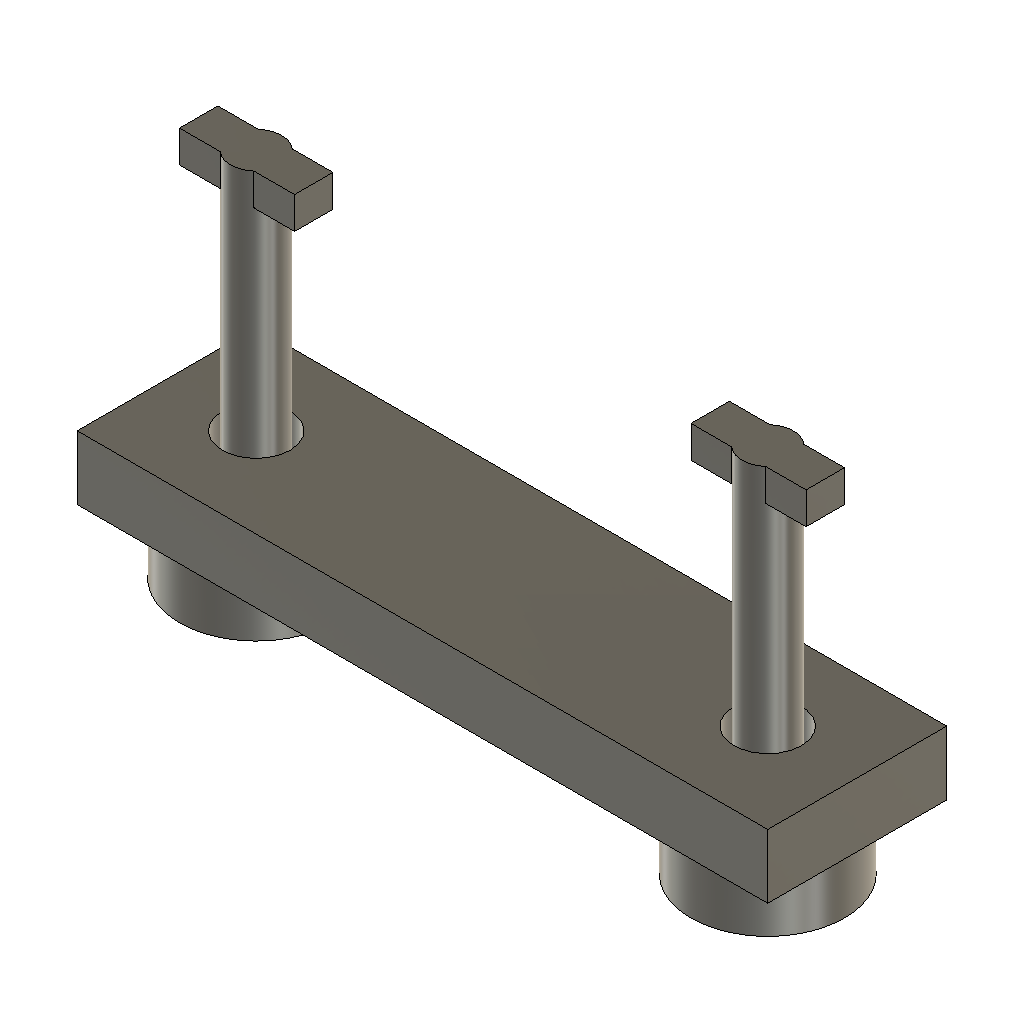
panel-handling-tool-concept (Autodesk Fusion 360 design; units mm, degrees)
part number: 2026-10-31-10-05-27-042
part number: 2026-10-31-10-05-27-360
part number: 2026-10-31-10-05-27-543
part number: 2026-10-31-10-05-28-223
part number: 2026-10-31-10-05-28-987
part number: 2026-10-31-10-05-30-686
part number: 2026-10-31-10-05-32-516
part number: 2026-10-31-10-05-34-265
Autodesk Fusion 360 part; units mm, degrees
ref_plane "WorkPlane1" through (0, 0, -16) normal (0, 0, 1) x (1, 0, 0) in component "PRINT handle bridge"
sketch "Front handle bridge sketch" plane through (0, 0, -16) normal (0, 0, 1) x (1, 0, 0) in component "PRINT handle bridge"
  line L0 (-7, -7) -> (47, -7)
  line L1 (47, -7) -> (47, 7)
  line L2 (47, 7) -> (-7, 7)
  line L3 (-7, 7) -> (-7, -7)
  dimension "d70" = 7
  dimension "d71" = 7
  dimension "d72" = 54
  dimension "d73" = 14
  constraint horizontal L0
  constraint vertical L1
  constraint horizontal L2
  constraint vertical L3
  measures "d70" horizontal distance of origin L0.start
  measures "d71" vertical distance of origin L0.start
  measures "d72" horizontal distance of L0.start L0.end
  measures "d73" vertical distance of L0.end L1.end
extrude "Front handle bridge" add sketch "Front handle bridge sketch" along normal blind 5 makes body 1 in component "PRINT handle bridge"
ref_plane "WorkPlane2" through (0, 0, -16) normal (0, 0, 1) x (1, 0, 0) in component "PRINT handle bridge"
sketch "Rotating key and assembly clearance sketch" plane through (0, 0, -16) normal (0, 0, 1) x (1, 0, 0) in component "PRINT handle bridge"
  circle A0 centre (0, 0) radius 2.65
  dimension "d78" = 5.3
  constraint coincident A0.centre origin
  measures "d78" diameter of A0
extrude "Rotating key and assembly clearance" cut sketch "Rotating key and assembly clearance sketch" along normal blind 5 bodies 1 in component "PRINT handle bridge"
ref_plane "WorkPlane1" through (0, 0, -16) normal (0, 0, 1) x (1, 0, 0) in component "PRINT quarter-turn key 0 mm"
sketch "Key shaft sketch" plane through (0, 0, -16) normal (0, 0, 1) x (1, 0, 0) in component "PRINT quarter-turn key 0 mm"
  circle A0 centre (0, 0) radius 2
  dimension "d83" = 4
  constraint coincident A0.centre origin
  measures "d83" diameter of A0
extrude "Key shaft" add sketch "Key shaft sketch" along normal blind 24 separate body makes body 2 in component "PRINT quarter-turn key 0 mm"
ref_plane "WorkPlane2" through (0, 0, -18) normal (0, 0, 1) x (1, 0, 0) in component "PRINT quarter-turn key 0 mm"
sketch "Square knob drive sketch" plane through (0, 0, -18) normal (0, 0, 1) x (1, 0, 0) in component "PRINT quarter-turn key 0 mm"
  line L0 (-1.8, -1.8) -> (1.8, -1.8)
  line L1 (1.8, -1.8) -> (1.8, 1.8)
  line L2 (1.8, 1.8) -> (-1.8, 1.8)
  line L3 (-1.8, 1.8) -> (-1.8, -1.8)
  dimension "d88" = 1.8
  dimension "d89" = 1.8
  dimension "d90" = 3.6
  dimension "d91" = 3.6
  constraint horizontal L0
  constraint vertical L1
  constraint horizontal L2
  constraint vertical L3
  measures "d88" horizontal distance of origin L0.start
  measures "d89" vertical distance of origin L0.start
  measures "d90" horizontal distance of L0.start L0.end
  measures "d91" vertical distance of L0.end L1.end
extrude "Square knob drive" add sketch "Square knob drive sketch" along normal blind 2 bodies 2 in component "PRINT quarter-turn key 0 mm"
ref_plane "WorkPlane3" through (0, 0, -18) normal (0, 0, 1) x (1, 0, 0) in component "PRINT quarter-turn key 0 mm"
sketch "M2 pilot - tapping trial required sketch" plane through (0, 0, -18) normal (0, 0, 1) x (1, 0, 0) in component "PRINT quarter-turn key 0 mm"
  circle A0 centre (0, 0) radius 0.8
  dimension "d96" = 1.6
  constraint coincident A0.centre origin
  measures "d96" diameter of A0
extrude "M2 pilot - tapping trial required" cut sketch "M2 pilot - tapping trial required sketch" along normal blind 6 bodies 2 in component "PRINT quarter-turn key 0 mm"
ref_plane "WorkPlane4" through (0, 0, 5.5) normal (0, 0, 1) x (1, 0, 0) in component "PRINT quarter-turn key 0 mm"
sketch "Locked transverse bearing tab sketch" plane through (0, 0, 5.5) normal (0, 0, 1) x (1, 0, 0) in component "PRINT quarter-turn key 0 mm"
  line L0 (-4.5, -1.5) -> (4.5, -1.5)
  line L1 (4.5, -1.5) -> (4.5, 1.5)
  line L2 (4.5, 1.5) -> (-4.5, 1.5)
  line L3 (-4.5, 1.5) -> (-4.5, -1.5)
  dimension "d101" = 4.5
  dimension "d102" = 1.5
  dimension "d103" = 9
  dimension "d104" = 3
  constraint horizontal L0
  constraint vertical L1
  constraint horizontal L2
  constraint vertical L3
  measures "d101" horizontal distance of origin L0.start
  measures "d102" vertical distance of origin L0.start
  measures "d103" horizontal distance of L0.start L0.end
  measures "d104" vertical distance of L0.end L1.end
extrude "Locked transverse bearing tab" add sketch "Locked transverse bearing tab sketch" along normal blind 2.5 bodies 2 in component "PRINT quarter-turn key 0 mm"
ref_plane "WorkPlane1" through (0, 0, -21) normal (0, 0, 1) x (1, 0, 0) in component "PRINT thumb knob 0 mm"
sketch "Separate thumb knob sketch" plane through (0, 0, -21) normal (0, 0, 1) x (1, 0, 0) in component "PRINT thumb knob 0 mm"
  circle A0 centre (0, 0) radius 6
  dimension "d109" = 12
  constraint coincident A0.centre origin
  measures "d109" diameter of A0
extrude "Separate thumb knob" add sketch "Separate thumb knob sketch" along normal blind 5 separate body makes body 3 in component "PRINT thumb knob 0 mm"
ref_plane "WorkPlane2" through (0, 0, -16) normal (0, 0, 1) x (1, 0, 0) in component "PRINT thumb knob 0 mm"
sketch "Square drive socket sketch" plane through (0, 0, -16) normal (0, 0, 1) x (1, 0, 0) in component "PRINT thumb knob 0 mm"
  line L0 (-1.9, -1.9) -> (1.9, -1.9)
  line L1 (1.9, -1.9) -> (1.9, 1.9)
  line L2 (1.9, 1.9) -> (-1.9, 1.9)
  line L3 (-1.9, 1.9) -> (-1.9, -1.9)
  dimension "d114" = 1.9
  dimension "d115" = 1.9
  dimension "d116" = 3.8
  dimension "d117" = 3.8
  constraint horizontal L0
  constraint vertical L1
  constraint horizontal L2
  constraint vertical L3
  measures "d114" horizontal distance of origin L0.start
  measures "d115" vertical distance of origin L0.start
  measures "d116" horizontal distance of L0.start L0.end
  measures "d117" vertical distance of L0.end L1.end
extrude "Square drive socket" cut sketch "Square drive socket sketch" against normal blind 2.2 bodies 3 in component "PRINT thumb knob 0 mm"
ref_plane "WorkPlane3" through (0, 0, -21) normal (0, 0, 1) x (1, 0, 0) in component "PRINT thumb knob 0 mm"
sketch "M2 fixing clearance sketch" plane through (0, 0, -21) normal (0, 0, 1) x (1, 0, 0) in component "PRINT thumb knob 0 mm"
  circle A0 centre (0, 0) radius 1.2
  dimension "d122" = 2.4
  constraint coincident A0.centre origin
  measures "d122" diameter of A0
extrude "M2 fixing clearance" cut sketch "M2 fixing clearance sketch" along normal blind 5 bodies 3 in component "PRINT thumb knob 0 mm"
ref_plane "WorkPlane4" through (0, 0, -21) normal (0, 0, 1) x (1, 0, 0) in component "PRINT thumb knob 0 mm"
sketch "M2 flush head recess sketch" plane through (0, 0, -21) normal (0, 0, 1) x (1, 0, 0) in component "PRINT thumb knob 0 mm"
  circle A0 centre (0, 0) radius 2
  dimension "d127" = 4
  constraint coincident A0.centre origin
  measures "d127" diameter of A0
extrude "M2 flush head recess" cut sketch "M2 flush head recess sketch" along normal blind 0.8 draft -45 bodies 3 in component "PRINT thumb knob 0 mm"
ref_plane "WorkPlane1" through (0, 0, -20.9) normal (0, 0, 1) x (1, 0, 0) in component "REFERENCE handle M2x6 0 mm"
sketch "Nominal 90 degree head sketch" plane through (0, 0, -20.9) normal (0, 0, 1) x (1, 0, 0) in component "REFERENCE handle M2x6 0 mm"
  circle A0 centre (0, 0) radius 1.9
  dimension "d132" = 3.8
  constraint coincident A0.centre origin
  measures "d132" diameter of A0
extrude "Nominal 90 degree head" add sketch "Nominal 90 degree head sketch" along normal blind 0.9 draft -45 separate body makes body 4 in component "REFERENCE handle M2x6 0 mm"
ref_plane "WorkPlane2" through (0, 0, -20) normal (0, 0, 1) x (1, 0, 0) in component "REFERENCE handle M2x6 0 mm"
sketch "Unthreaded major-diameter envelope sketch" plane through (0, 0, -20) normal (0, 0, 1) x (1, 0, 0) in component "REFERENCE handle M2x6 0 mm"
  circle A0 centre (0, 0) radius 1
  dimension "d137" = 2
  constraint coincident A0.centre origin
  measures "d137" diameter of A0
extrude "Unthreaded major-diameter envelope" add sketch "Unthreaded major-diameter envelope sketch" along normal blind 5.1 bodies 4 in component "REFERENCE handle M2x6 0 mm"
ref_plane "WorkPlane3" through (0, 0, -20.9) normal (0, 0, 1) x (1, 0, 0) in component "REFERENCE handle M2x6 0 mm"
sketch "Cross drive envelope sketch" plane through (0, 0, -20.9) normal (0, 0, 1) x (1, 0, 0) in component "REFERENCE handle M2x6 0 mm"
  line L0 (-0.275, -1.14) -> (0.275, -1.14)
  line L1 (0.275, -1.14) -> (0.275, 1.14)
  line L2 (0.275, 1.14) -> (-0.275, 1.14)
  line L3 (-0.275, 1.14) -> (-0.275, -1.14)
  dimension "d142" = 0.275
  dimension "d143" = 1.14
  dimension "d144" = 0.55
  dimension "d145" = 2.28
  constraint horizontal L0
  constraint vertical L1
  constraint horizontal L2
  constraint vertical L3
  measures "d142" horizontal distance of origin L0.start
  measures "d143" vertical distance of origin L0.start
  measures "d144" horizontal distance of L0.start L0.end
  measures "d145" vertical distance of L0.end L1.end
extrude "Cross drive envelope" cut sketch "Cross drive envelope sketch" along normal blind 0.35 bodies 4 in component "REFERENCE handle M2x6 0 mm"
ref_plane "WorkPlane4" through (0, 0, -20.9) normal (0, 0, 1) x (1, 0, 0) in component "REFERENCE handle M2x6 0 mm"
sketch "Cross drive envelope sketch (1)" plane through (0, 0, -20.9) normal (0, 0, 1) x (1, 0, 0) in component "REFERENCE handle M2x6 0 mm"
  line L0 (-1.14, -0.275) -> (1.14, -0.275)
  line L1 (1.14, -0.275) -> (1.14, 0.275)
  line L2 (1.14, 0.275) -> (-1.14, 0.275)
  line L3 (-1.14, 0.275) -> (-1.14, -0.275)
  dimension "d150" = 1.14
  dimension "d151" = 0.275
  dimension "d152" = 2.28
  dimension "d153" = 0.55
  constraint horizontal L0
  constraint vertical L1
  constraint horizontal L2
  constraint vertical L3
  measures "d150" horizontal distance of origin L0.start
  measures "d151" vertical distance of origin L0.start
  measures "d152" horizontal distance of L0.start L0.end
  measures "d153" vertical distance of L0.end L1.end
extrude "Cross drive envelope (1)" cut sketch "Cross drive envelope sketch (1)" along normal blind 0.35 bodies 4 in component "REFERENCE handle M2x6 0 mm"
ref_plane "WorkPlane3" through (0, 0, -16) normal (0, 0, 1) x (1, 0, 0) in component "PRINT handle bridge"
sketch "Rotating key and assembly clearance sketch (1)" plane through (0, 0, -16) normal (0, 0, 1) x (1, 0, 0) in component "PRINT handle bridge"
  circle A0 centre (40, 0) radius 2.65
  dimension "d158" = 40
  dimension "d159" = 5.3
  constraint horizontal origin A0.centre
  measures "d158" horizontal distance of origin A0.centre
  measures "d159" diameter of A0
extrude "Rotating key and assembly clearance (1)" cut sketch "Rotating key and assembly clearance sketch (1)" along normal blind 5 bodies 1 in component "PRINT handle bridge"
ref_plane "WorkPlane1" through (0, 0, -16) normal (0, 0, 1) x (1, 0, 0) in component "PRINT quarter-turn key handlePitch"
sketch "Key shaft sketch (2)" plane through (0, 0, -16) normal (0, 0, 1) x (1, 0, 0) in component "PRINT quarter-turn key handlePitch"
  circle A0 centre (40, 0) radius 2
  dimension "d164" = 40
  dimension "d165" = 4
  constraint horizontal origin A0.centre
  measures "d164" horizontal distance of origin A0.centre
  measures "d165" diameter of A0
extrude "Key shaft'" add sketch "Key shaft sketch (2)" along normal blind 24 separate body makes body 5 in component "PRINT quarter-turn key handlePitch"
ref_plane "WorkPlane2" through (0, 0, -18) normal (0, 0, 1) x (1, 0, 0) in component "PRINT quarter-turn key handlePitch"
sketch "Square knob drive sketch (2)" plane through (0, 0, -18) normal (0, 0, 1) x (1, 0, 0) in component "PRINT quarter-turn key handlePitch"
  line L0 (38.2, -1.8) -> (41.8, -1.8)
  line L1 (41.8, -1.8) -> (41.8, 1.8)
  line L2 (41.8, 1.8) -> (38.2, 1.8)
  line L3 (38.2, 1.8) -> (38.2, -1.8)
  dimension "d170" = 38.2
  dimension "d171" = 1.8
  dimension "d172" = 3.6
  dimension "d173" = 3.6
  constraint horizontal L0
  constraint vertical L1
  constraint horizontal L2
  constraint vertical L3
  measures "d170" horizontal distance of origin L0.start
  measures "d171" vertical distance of origin L0.start
  measures "d172" horizontal distance of L0.start L0.end
  measures "d173" vertical distance of L0.end L1.end
extrude "Square knob drive'" add sketch "Square knob drive sketch (2)" along normal blind 2 bodies 5 in component "PRINT quarter-turn key handlePitch"
ref_plane "WorkPlane3" through (0, 0, -18) normal (0, 0, 1) x (1, 0, 0) in component "PRINT quarter-turn key handlePitch"
sketch "M2 pilot - tapping trial required sketch (2)" plane through (0, 0, -18) normal (0, 0, 1) x (1, 0, 0) in component "PRINT quarter-turn key handlePitch"
  circle A0 centre (40, 0) radius 0.8
  dimension "d178" = 40
  dimension "d179" = 1.6
  constraint horizontal origin A0.centre
  measures "d178" horizontal distance of origin A0.centre
  measures "d179" diameter of A0
extrude "M2 pilot - tapping trial required'" cut sketch "M2 pilot - tapping trial required sketch (2)" along normal blind 6 bodies 5 in component "PRINT quarter-turn key handlePitch"
ref_plane "WorkPlane4" through (0, 0, 5.5) normal (0, 0, 1) x (1, 0, 0) in component "PRINT quarter-turn key handlePitch"
sketch "Locked transverse bearing tab sketch (2)" plane through (0, 0, 5.5) normal (0, 0, 1) x (1, 0, 0) in component "PRINT quarter-turn key handlePitch"
  line L0 (35.5, -1.5) -> (44.5, -1.5)
  line L1 (44.5, -1.5) -> (44.5, 1.5)
  line L2 (44.5, 1.5) -> (35.5, 1.5)
  line L3 (35.5, 1.5) -> (35.5, -1.5)
  dimension "d184" = 35.5
  dimension "d185" = 1.5
  dimension "d186" = 9
  dimension "d187" = 3
  constraint horizontal L0
  constraint vertical L1
  constraint horizontal L2
  constraint vertical L3
  measures "d184" horizontal distance of origin L0.start
  measures "d185" vertical distance of origin L0.start
  measures "d186" horizontal distance of L0.start L0.end
  measures "d187" vertical distance of L0.end L1.end
extrude "Locked transverse bearing tab'" add sketch "Locked transverse bearing tab sketch (2)" along normal blind 2.5 bodies 5 in component "PRINT quarter-turn key handlePitch"
ref_plane "WorkPlane1" through (0, 0, -21) normal (0, 0, 1) x (1, 0, 0) in component "PRINT thumb knob handlePitch"
sketch "Separate thumb knob sketch (2)" plane through (0, 0, -21) normal (0, 0, 1) x (1, 0, 0) in component "PRINT thumb knob handlePitch"
  circle A0 centre (40, 0) radius 6
  dimension "d192" = 40
  dimension "d193" = 12
  constraint horizontal origin A0.centre
  measures "d192" horizontal distance of origin A0.centre
  measures "d193" diameter of A0
extrude "Separate thumb knob'" add sketch "Separate thumb knob sketch (2)" along normal blind 5 separate body makes body 6 in component "PRINT thumb knob handlePitch"
ref_plane "WorkPlane2" through (0, 0, -16) normal (0, 0, 1) x (1, 0, 0) in component "PRINT thumb knob handlePitch"
sketch "Square drive socket sketch (2)" plane through (0, 0, -16) normal (0, 0, 1) x (1, 0, 0) in component "PRINT thumb knob handlePitch"
  line L0 (38.1, -1.9) -> (41.9, -1.9)
  line L1 (41.9, -1.9) -> (41.9, 1.9)
  line L2 (41.9, 1.9) -> (38.1, 1.9)
  line L3 (38.1, 1.9) -> (38.1, -1.9)
  dimension "d198" = 38.1
  dimension "d199" = 1.9
  dimension "d200" = 3.8
  dimension "d201" = 3.8
  constraint horizontal L0
  constraint vertical L1
  constraint horizontal L2
  constraint vertical L3
  measures "d198" horizontal distance of origin L0.start
  measures "d199" vertical distance of origin L0.start
  measures "d200" horizontal distance of L0.start L0.end
  measures "d201" vertical distance of L0.end L1.end
extrude "Square drive socket'" cut sketch "Square drive socket sketch (2)" against normal blind 2.2 bodies 6 in component "PRINT thumb knob handlePitch"
ref_plane "WorkPlane3" through (0, 0, -21) normal (0, 0, 1) x (1, 0, 0) in component "PRINT thumb knob handlePitch"
sketch "M2 fixing clearance sketch (2)" plane through (0, 0, -21) normal (0, 0, 1) x (1, 0, 0) in component "PRINT thumb knob handlePitch"
  circle A0 centre (40, 0) radius 1.2
  dimension "d206" = 40
  dimension "d207" = 2.4
  constraint horizontal origin A0.centre
  measures "d206" horizontal distance of origin A0.centre
  measures "d207" diameter of A0
extrude "M2 fixing clearance'" cut sketch "M2 fixing clearance sketch (2)" along normal blind 5 bodies 6 in component "PRINT thumb knob handlePitch"
ref_plane "WorkPlane4" through (0, 0, -21) normal (0, 0, 1) x (1, 0, 0) in component "PRINT thumb knob handlePitch"
sketch "M2 flush head recess sketch (2)" plane through (0, 0, -21) normal (0, 0, 1) x (1, 0, 0) in component "PRINT thumb knob handlePitch"
  circle A0 centre (40, 0) radius 2
  dimension "d212" = 40
  dimension "d213" = 4
  constraint horizontal origin A0.centre
  measures "d212" horizontal distance of origin A0.centre
  measures "d213" diameter of A0
extrude "M2 flush head recess'" cut sketch "M2 flush head recess sketch (2)" along normal blind 0.8 draft -45 bodies 6 in component "PRINT thumb knob handlePitch"
ref_plane "WorkPlane1" through (0, 0, -20.9) normal (0, 0, 1) x (1, 0, 0) in component "REFERENCE handle M2x6 handlePitch"
sketch "Nominal 90 degree head sketch (2)" plane through (0, 0, -20.9) normal (0, 0, 1) x (1, 0, 0) in component "REFERENCE handle M2x6 handlePitch"
  circle A0 centre (40, 0) radius 1.9
  dimension "d218" = 40
  dimension "d219" = 3.8
  constraint horizontal origin A0.centre
  measures "d218" horizontal distance of origin A0.centre
  measures "d219" diameter of A0
extrude "Nominal 90 degree head'" add sketch "Nominal 90 degree head sketch (2)" along normal blind 0.9 draft -45 separate body makes body 7 in component "REFERENCE handle M2x6 handlePitch"
ref_plane "WorkPlane2" through (0, 0, -20) normal (0, 0, 1) x (1, 0, 0) in component "REFERENCE handle M2x6 handlePitch"
sketch "Unthreaded major-diameter envelope sketch (2)" plane through (0, 0, -20) normal (0, 0, 1) x (1, 0, 0) in component "REFERENCE handle M2x6 handlePitch"
  circle A0 centre (40, 0) radius 1
  dimension "d224" = 40
  dimension "d225" = 2
  constraint horizontal origin A0.centre
  measures "d224" horizontal distance of origin A0.centre
  measures "d225" diameter of A0
extrude "Unthreaded major-diameter envelope'" add sketch "Unthreaded major-diameter envelope sketch (2)" along normal blind 5.1 bodies 7 in component "REFERENCE handle M2x6 handlePitch"
ref_plane "WorkPlane3" through (0, 0, -20.9) normal (0, 0, 1) x (1, 0, 0) in component "REFERENCE handle M2x6 handlePitch"
sketch "Cross drive envelope sketch (2)" plane through (0, 0, -20.9) normal (0, 0, 1) x (1, 0, 0) in component "REFERENCE handle M2x6 handlePitch"
  line L0 (39.725, -1.14) -> (40.275, -1.14)
  line L1 (40.275, -1.14) -> (40.275, 1.14)
  line L2 (40.275, 1.14) -> (39.725, 1.14)
  line L3 (39.725, 1.14) -> (39.725, -1.14)
  dimension "d230" = 39.725
  dimension "d231" = 1.14
  dimension "d232" = 0.55
  dimension "d233" = 2.28
  constraint horizontal L0
  constraint vertical L1
  constraint horizontal L2
  constraint vertical L3
  measures "d230" horizontal distance of origin L0.start
  measures "d231" vertical distance of origin L0.start
  measures "d232" horizontal distance of L0.start L0.end
  measures "d233" vertical distance of L0.end L1.end
extrude "Cross drive envelope'" cut sketch "Cross drive envelope sketch (2)" along normal blind 0.35 bodies 7 in component "REFERENCE handle M2x6 handlePitch"
ref_plane "WorkPlane4" through (0, 0, -20.9) normal (0, 0, 1) x (1, 0, 0) in component "REFERENCE handle M2x6 handlePitch"
sketch "Cross drive envelope sketch (1) (2)" plane through (0, 0, -20.9) normal (0, 0, 1) x (1, 0, 0) in component "REFERENCE handle M2x6 handlePitch"
  line L0 (38.86, -0.275) -> (41.14, -0.275)
  line L1 (41.14, -0.275) -> (41.14, 0.275)
  line L2 (41.14, 0.275) -> (38.86, 0.275)
  line L3 (38.86, 0.275) -> (38.86, -0.275)
  dimension "d238" = 38.86
  dimension "d239" = 0.275
  dimension "d240" = 2.28
  dimension "d241" = 0.55
  constraint horizontal L0
  constraint vertical L1
  constraint horizontal L2
  constraint vertical L3
  measures "d238" horizontal distance of origin L0.start
  measures "d239" vertical distance of origin L0.start
  measures "d240" horizontal distance of L0.start L0.end
  measures "d241" vertical distance of L0.end L1.end
extrude "Cross drive envelope (1)'" cut sketch "Cross drive envelope sketch (1) (2)" along normal blind 0.35 bodies 7 in component "REFERENCE handle M2x6 handlePitch"
component "PRINT handle bridge" placed x (1, 0, 0) y (0, 1, 0) z (0, 0, 1) at (0, 0, 0)
component "PRINT quarter-turn key 0 mm" placed x (1, 0, 0) y (0, 1, 0) z (0, 0, 1) at (0, 0, 0)
component "PRINT thumb knob 0 mm" placed x (1, 0, 0) y (0, 1, 0) z (0, 0, 1) at (0, 0, 0)
component "REFERENCE handle M2x6 0 mm" placed x (1, 0, 0) y (0, 1, 0) z (0, 0, 1) at (0, 0, 0)
component "PRINT quarter-turn key handlePitch" placed x (1, 0, 0) y (0, 1, 0) z (0, 0, 1) at (0, 0, 0)
component "PRINT thumb knob handlePitch" placed x (1, 0, 0) y (0, 1, 0) z (0, 0, 1) at (0, 0, 0)
component "REFERENCE handle M2x6 handlePitch" placed x (1, 0, 0) y (0, 1, 0) z (0, 0, 1) at (0, 0, 0)
equation "columns = 12" comment "Even integer 4..14; each cell is 20 mm"
equation "rows = 12" comment "Even integer 4..14"
equation "pitch = 20 mm" comment "Keep for dense SKADIS compatible lattice"
equation "panelWidth = columns * pitch" comment "Nominal module pitch X"
equation "panelHeight = rows * pitch" comment "Nominal module pitch Y"
equation "seamGap = 0.35 mm" comment "Physical envelope shrinks around fixed lattice"
equation "boardThickness = 5 mm" comment "Fit-test with real hooks"
equation "slotWidth = 5 mm" comment "Minimum throat width"
equation "slotHeight = 15 mm" comment "Minimum throat height"
equation "entryRadius = 0.4 mm" comment "Front slot and perimeter edge rounding"
equation "cornerRadius = 6 mm" comment "Plan-view panel corner rounding"
equation "hookClearance = 10 mm" comment "PROVISIONAL unobstructed depth behind board; carriers begin at its rear boundary"
equation "frameZ = carrierZ + carrierThickness" comment "Front extrusion datum"
equation "profileMouth = 6.28 mm" comment "User measured mouth"
equation "profileCavity = 11 mm" comment "User measured widest cavity"
equation "profileDepth = 6.2 mm" comment "User measured face-to-floor depth"
equation "profileFloor = 5.7 mm" comment "User estimate, lower confidence"
equation "profileLip = 1.5 mm" comment "Unmeasured; tentative comparable catalog value"
equation "profileTaperStart = profileDepth - ( profileCavity - profileFloor ) / 2" comment "Assumed 45-degree inner slopes"
equation "profileBore = 5 mm" comment "Unmeasured central bore, reference only"
equation "nutWidth = 8.8 mm" comment "Provisional low-profile METAL T-nut envelope, not old rectangular carrier"
equation "nutLength = 12 mm" comment "End-loaded anti-rotation metal nut envelope"
equation "nutThickness = 2.7 mm" comment "Thin nut reference; fit/load still unverified"
equation "jointLeg = 18 mm" comment "In-bay angle footprint"
equation "jointThickness = 3 mm" comment "Metal bracket thickness"
equation "jointDepth = 16 mm" comment "Bracket depth within 20 mm rail"
equation "sideScrewLength = 8 mm" comment "M5x8 reference; check against actual bracket and nut"
equation "wallTabHeight = 24 mm" comment "Tab along extrusion"
equation "wallTabReach = 22 mm" comment "Tab into open bay"
equation "wallAnchorClearance = 6.5 mm" comment "Placeholder wall anchor interface"
equation "wallDriverDiameter = 12 mm" comment "Clear tool envelope in open bays"
equation "keyDriverDiameter = 5 mm" comment "Short hex-key working-leg envelope"
equation "keyDriverReach = 20 mm" comment "Short hex-key working-leg reach"
equation "supportWidth = 3.2 mm" comment "Prototype blade; two perimeter lines need print review"
equation "supportLength = 12 mm" comment "Compression bearing length"
equation "hookEnvelopeWidth = 6 mm" comment "Conservative provisional continuous hook column"
equation "carrierThickness = 7 mm" comment "Room for captive M2 nut and stock M5x12"
equation "panelClearance = 2.4 mm" comment "M2 clearance"
equation "panelHeadPocket = 4 mm" comment "DIN965 3.8 mm head plus 0.1 mm recess"
equation "carrierHeadPocket = 9.4 mm" comment "DIN965 M5 9.2 mm head plus recess"
equation "carrierBore = 5.5 mm" comment "M5 clearance"
equation "tongueWidth = 2.8 mm" comment "Rear axial registration tongue"
equation "tongueLength = 8 mm" comment "Axial release registration"
equation "tongueDepth = 0.6 mm" comment "Tongue engagement"
equation "registerClearance = 0.2 mm" comment "Each side of printed tongue"
equation "carrierZ = boardThickness + hookClearance" comment "Rear hook cavity boundary"
equation "stepCorner = 0.6 mm" comment "Small plan corner relief; printed fit remains untested"
equation "handlePitch = 40 mm" comment "Use two A slots on one panel; clear surrounding artwork first"
equation "d70 = abs(-7 mm)"
equation "d71 = abs(-7 mm)"
equation "d72 = handlePitch + 14 mm"
equation "d88 = abs(0 mm - 1.8 mm)"
equation "d89 = abs(-1.8 mm)"
equation "d101 = abs(0 mm - 4.5 mm)"
equation "d102 = abs(-1.5 mm)"
equation "d114 = abs(0 mm - 1.9 mm)"
equation "d115 = abs(-1.9 mm)"
equation "d133 = ( 3.8 mm - 2 mm ) / 2"
equation "d135 = -20.9 mm + ( 3.8 mm - 2 mm ) / 2"
equation "d138 = 6 mm - ( 3.8 mm - 2 mm ) / 2"
equation "d142 = abs(0 mm - ( 0.55 mm ) / 2)"
equation "d143 = abs(0 mm - ( 3.8 mm * 0.6 ) / 2)"
equation "d145 = 3.8 mm * 0.6"
equation "d150 = abs(0 mm - ( 3.8 mm * 0.6 ) / 2)"
equation "d151 = abs(0 mm - ( 0.55 mm ) / 2)"
equation "d152 = 3.8 mm * 0.6"
equation "d158 = abs(handlePitch)"
equation "d164 = abs(handlePitch)"
equation "d170 = abs(handlePitch - 1.8 mm)"
equation "d171 = abs(-1.8 mm)"
equation "d178 = abs(handlePitch)"
equation "d184 = abs(handlePitch - 4.5 mm)"
equation "d185 = abs(-1.5 mm)"
equation "d192 = abs(handlePitch)"
equation "d198 = abs(handlePitch - 1.9 mm)"
equation "d199 = abs(-1.9 mm)"
equation "d206 = abs(handlePitch)"
equation "d212 = abs(handlePitch)"
equation "d218 = abs(handlePitch)"
equation "d220 = ( 3.8 mm - 2 mm ) / 2"
equation "d222 = -20.9 mm + ( 3.8 mm - 2 mm ) / 2"
equation "d224 = abs(handlePitch)"
equation "d226 = 6 mm - ( 3.8 mm - 2 mm ) / 2"
equation "d230 = abs(handlePitch - ( 0.55 mm ) / 2)"
equation "d231 = abs(0 mm - ( 3.8 mm * 0.6 ) / 2)"
equation "d233 = 3.8 mm * 0.6"
equation "d238 = abs(handlePitch - ( 3.8 mm * 0.6 ) / 2)"
equation "d239 = abs(0 mm - ( 0.55 mm ) / 2)"
equation "d240 = 3.8 mm * 0.6"
